gear-housing-lid (Autodesk Fusion 360 design; units mm, degrees)
part number: 2026-11-15-18-44-28-239
part number: 2026-11-15-19-43-16-400
part number: 2026-11-15-19-48-05-713
Autodesk Fusion 360 part; units mm, degrees
sketch "Sketch1" plane through (0, 0, 0) normal (0, 0, 1) x (1, 0, 0)
  line L0 (33, 38.3524) -> (-71.8855, 38.3524)
  line L1 (-30.0855, 26.3524) -> (-22.0855, 26.3524)
  circle A0 centre (29, -29) radius 2.6
  arc A1 (25, -23) -> (23, -25) centre (25, -25) ccw
  line L2 (23, -33) -> (-61.8855, -33)
  line L3 (-71.8855, -35) -> (33, -35)
  arc A2 (33, -35) -> (35, -33) centre (33, -33) ccw
  circle A3 centre (29, 32.3524) radius 2.6
  line L4 (23, 36.3524) -> (23, 28.3524)
  line L5 (-20.0855, 28.3524) -> (-20.0855, 36.3524)
  arc A4 (-71.8855, 38.3524) -> (-73.8855, 36.3524) centre (-71.8855, 36.3524) ccw
  line L6 (-63.8855, -23) -> (-71.8855, -23)
  line L7 (-71.8855, 36.3524) -> (-32.0855, 36.3524)
  line L8 (-71.8855, -23) -> (-71.8855, 36.3524)
  arc A5 (-73.8855, -33) -> (-71.8855, -35) centre (-71.8855, -33) ccw
  arc A6 (-32.0855, 28.3524) -> (-30.0855, 26.3524) centre (-30.0855, 28.3524) ccw
  line L9 (-73.8855, 36.3524) -> (-73.8855, -33)
  line L10 (-61.8855, -33) -> (-61.8855, -25)
  circle A7 centre (-67.8855, -29) radius 2.6
  arc A8 (-61.8855, -25) -> (-63.8855, -23) centre (-63.8855, -25) ccw
  circle A9 centre (-26.0855, 32.3524) radius 2.6
  arc A10 (35, 36.3524) -> (33, 38.3524) centre (33, 36.3524) ccw
  line L11 (33, 26.3524) -> (33, -23)
  arc A11 (-22.0855, 26.3524) -> (-20.0855, 28.3524) centre (-22.0855, 28.3524) ccw
  line L12 (-20.0855, 36.3524) -> (23, 36.3524)
  line L13 (33, -23) -> (25, -23)
  arc A12 (23, 28.3524) -> (25, 26.3524) centre (25, 28.3524) ccw
  line L14 (25, 26.3524) -> (33, 26.3524)
  line L15 (23, -25) -> (23, -33)
  line L16 (-32.0855, 36.3524) -> (-32.0855, 28.3524)
  line L17 (35, -33) -> (35, 36.3524)
  arc A13 (-33.6855, 28.3524) -> (-30.0855, 24.7524) centre (-30.0855, 28.3524) ccw
  line L18 (-30.0855, 24.7524) -> (-22.0855, 24.7524)
  arc A14 (-22.0855, 24.7524) -> (-18.4855, 28.3524) centre (-22.0855, 28.3524) ccw
  line L19 (-18.4855, 28.3524) -> (-18.4855, 34.7524)
  line L20 (-18.4855, 34.7524) -> (21.4, 34.7524)
  line L21 (21.4, 34.7524) -> (21.4, 28.3524)
  arc A15 (21.4, 28.3524) -> (25, 24.7524) centre (25, 28.3524) ccw
  line L22 (25, 24.7524) -> (31.4, 24.7524)
  line L23 (31.4, 24.7524) -> (31.4, -21.4)
  line L24 (31.4, -21.4) -> (25, -21.4)
  arc A16 (25, -21.4) -> (21.4, -25) centre (25, -25) ccw
  line L25 (21.4, -25) -> (21.4, -31.4)
  line L26 (21.4, -31.4) -> (-60.2855, -31.4)
  line L27 (-60.2855, -31.4) -> (-60.2855, -25)
  arc A17 (-60.2855, -25) -> (-63.8855, -21.4) centre (-63.8855, -25) ccw
  line L28 (-63.8855, -21.4) -> (-70.2855, -21.4)
  line L29 (-70.2855, -21.4) -> (-70.2855, 34.7524)
  line L30 (-70.2855, 34.7524) -> (-33.6855, 34.7524)
  line L31 (-33.6855, 34.7524) -> (-33.6855, 28.3524)
  circle A18 centre (0, 0) radius 3.45
  circle A19 centre (0, 0) radius 4
  circle A20 centre (-26.0855, 32.3524) radius 2.6
  circle A21 centre (-0.005, 0.0025) radius 7
  line L32 (-32.0855, 36.3524) -> (-32.0855, 28.3524)
  line L33 (-61.8855, -33) -> (-61.8855, -25)
  line L34 (-71.8855, -35) -> (33, -35)
  line L35 (33, 38.3524) -> (-71.8855, 38.3524)
  line L36 (23, -33) -> (-61.8855, -33)
  line L37 (-30.0855, 26.3524) -> (-22.0855, 26.3524)
  line L38 (23, 36.3524) -> (23, 28.3524)
  line L39 (25, 26.3524) -> (33, 26.3524)
  line L40 (35, -33) -> (35, 36.3524)
  circle A22 centre (29, 32.3524) radius 2.6
  line L41 (-63.8855, -23) -> (-71.8855, -23)
  arc A23 (33, -35) -> (35, -33) centre (33, -33) ccw
  arc A24 (35, 36.3524) -> (33, 38.3524) centre (33, 36.3524) ccw
  line L42 (-73.8855, 36.3524) -> (-73.8855, -33)
  line L43 (23, -25) -> (23, -33)
  arc A25 (-71.8855, 38.3524) -> (-73.8855, 36.3524) centre (-71.8855, 36.3524) ccw
  arc A26 (-73.8855, -33) -> (-71.8855, -35) centre (-71.8855, -33) ccw
  line L44 (33, 26.3524) -> (33, -23)
  arc A27 (23, 28.3524) -> (25, 26.3524) centre (25, 28.3524) ccw
  arc A28 (-32.0855, 28.3524) -> (-30.0855, 26.3524) centre (-30.0855, 28.3524) ccw
  circle A29 centre (-67.8855, -29) radius 2.6
  line L45 (-20.0855, 36.3524) -> (23, 36.3524)
  arc A30 (-61.8855, -25) -> (-63.8855, -23) centre (-63.8855, -25) ccw
  line L46 (33, -23) -> (25, -23)
  line L47 (-20.0855, 28.3524) -> (-20.0855, 36.3524)
  arc A31 (-22.0855, 26.3524) -> (-20.0855, 28.3524) centre (-22.0855, 28.3524) ccw
  circle A32 centre (29, -29) radius 2.6
  arc A33 (25, -23) -> (23, -25) centre (25, -25) ccw
  line L48 (-71.8855, 36.3524) -> (-32.0855, 36.3524)
  line L49 (-71.8855, -23) -> (-71.8855, 36.3524)
  dimension "d3" = 1.6
  dimension "d6" = 6.9
  dimension "d7" = 8
  constraint coincident A18.centre A19.centre
  constraint concentric A18 A19
  measures "d6" diameter of A18
  measures "d7" diameter of A19
extrude "Extrude1" add sketch "Sketch1" against normal blind 1.6 contours L0 L3 A2 A4 A5 L9 A10 L17 L34 L35 L40 A23 A24 L42 A25 A26 | L1 A1 L2 L4 L5 L6 L7 L8 A6 L10 A8 L11 A11 L12 L13 A12 L14 L15 L16 L32 L33 L36 L37 L38 L39 L41 L43 L44 A27 A28 L45 A30 L46 L47 A31 A33 L48 L49 | A13 L18 A14 L19 L20 L21 A15 L22 L23 L24 A16 L25 L26 L27 A17 L28 L29 L30 L31 | A18 | A19 | A21 makes body 1
extrude "Extrude2" add sketch "Sketch1" along normal blind 5 contours L1 A1 L2 L4 L5 L6 L7 L8 A6 L10 A8 L11 A11 L12 L13 A12 L14 L15 L16 L32 L33 L36 L37 L38 L39 L41 L43 L44 A27 A28 L45 A30 L46 L47 A31 A33 L48 L49 bodies 1
extrude "Extrude3" add sketch "Sketch1" along normal blind 5.5 contours A18 bodies 1
extrude "Extrude4" add sketch "Sketch1" along normal blind 0.5 contours A19 bodies 1
mirror "Mirror1" about plane through (-71.8855, -35, 0) normal (0, -1, 0) of bodies 1 makes body 2
move_body "Move1" bodies 2 to x (1, 0, 0) y (0, 1, 0) z (0, 0, 1) at (0, -10, 0)
copy_body "Body->Comp1" bodies 2 removing the originals makes body 3 in component "Left"
copy_body "Body->Comp2" bodies 1 removing the originals makes body 4 in component "Right"
component "Left" placed x (1, 0, 0) y (0, 1, 0) z (0, 0, 1) at (0, 0, 0)
component "Right" placed x (1, 0, 0) y (0, 1, 0) z (0, 0, 1) at (0, 0, 0)
